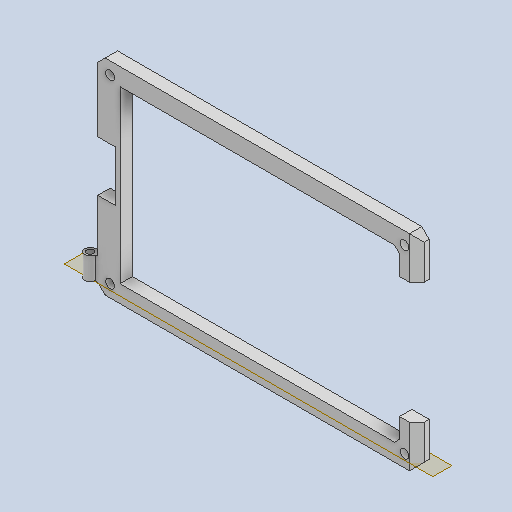
# Autodesk Inventor part: cap
Saved by Autodesk Inventor 2025 (Build 290162000, 162)
## iProperties
Created: 2026-10-22
Part Number: cap
Material: Типовые
Document SubType Name: Modeling
Designer: Leva
Density: 1 g/cm^3
Appearance: По умолчанию
Author: Leva
Autodesk Inventor part; units mm, degrees
ref_plane "YZ Plane" through (0, 0, 0) normal (1, 0, 0) x (0, 1, 0)
ref_plane "XZ Plane" through (0, 0, 0) normal (0, 1, 0) x (-1, 0, 0)
ref_plane "XY Plane" through (0, 0, 0) normal (0, 0, 1) x (1, 0, 0)
sketch "Эскиз1" plane through (0, 0, 0) normal (0, 0, 1) x (1, 0, 0)
  line L0 (82.923, -27.9995) -> (82.923, 49.0005) projected
  line L1 (85.923, 52.0005) -> (208.923, 52.0005) projected
  line L2 (211.923, 49.0005) -> (211.923, -27.9995) projected
  line L3 (208.923, -30.9995) -> (85.923, -30.9995) projected
  circle A0 centre (206.923, 47.0005) radius 1.35 construction
  circle A1 centre (87.923, 47.0005) radius 1.35 construction
  circle A2 centre (87.923, -25.9995) radius 1.35 construction
  circle A3 centre (206.923, -25.9995) radius 1.35 construction
  line L4 (204.923, -21.9995) -> (204.923, 43.0005)
  line L5 (202.923, 45.0005) -> (91.923, 45.0005)
  line L6 (89.923, 43.0005) -> (89.923, -21.9995)
  line L7 (91.923, -23.9995) -> (202.923, -23.9995)
  line L8 (204.923, -21.9995) -> (202.923, -23.9995)
  line L9 (204.923, 43.0005) -> (202.923, 45.0005)
  line L10 (91.923, 45.0005) -> (89.923, 43.0005)
  line L11 (91.923, -23.9995) -> (89.923, -21.9995)
  circle A4 centre (206.923, -25.9995) radius 1.8
  circle A5 centre (206.923, 47.0005) radius 1.8
  circle A6 centre (87.923, -25.9995) radius 1.8
  line L12 (85.923, 52.0005) -> (82.923, 49.0005) projected
  line L13 (211.923, 49.0005) -> (208.923, 52.0005) projected
  line L14 (208.923, -30.9995) -> (211.923, -27.9995) projected
  line L15 (82.923, -27.9995) -> (85.923, -30.9995) projected
  circle A7 centre (87.923, 47.0005) radius 1.8
  line L16 (204.923, -21.9995) -> (204.923, -13.9995) construction
  line L17 (204.923, -13.9995) -> (211.923, -13.9995)
  line L18 (211.923, 10.5005) -> (82.923, 10.5005) construction
  line L19 (204.923, 35.0005) -> (211.923, 35.0005)
  line L20 (83.923, 4.4505) -> (89.023, 4.4505) projected
  line L21 (89.023, 20.9105) -> (83.923, 20.9105) projected
  line L22 (83.923, 4.4505) -> (82.923, 4.4505) construction
  line L23 (82.923, 4.4505) -> (82.923, 2.4505) construction
  line L24 (82.923, 2.4505) -> (83.923, 2.4505) construction
  line L25 (83.923, 2.4505) -> (83.923, 4.4505) construction
  line L26 (82.923, 2.4505) -> (89.923, 2.4505)
  line L27 (83.923, 4.4505) -> (83.923, 20.651) construction
  line L28 (83.923, 20.9105) -> (82.923, 20.9105) construction
  line L29 (82.923, 20.9105) -> (82.923, 22.9105) construction
  line L30 (82.923, 22.9105) -> (83.923, 22.9105) construction
  line L31 (83.923, 22.9105) -> (83.923, 20.9105) construction
  line L32 (82.923, 22.9105) -> (89.923, 22.9105)
  line L33 (91.923, -23.9995) -> (91.923, 45.0005)
  point P0 (0, 0)
  point P1 (204.923, -23.9995)
  point P2 (204.923, 45.0005)
  point P3 (89.923, 45.0005)
  point P4 (89.923, -23.9995)
  point P5 (211.923, 35.0005)
  dimension "d0" = 7
  dimension "d1" = 2
  dimension "d2" = 2
  dimension "d3" = 2
  dimension "d4" = 2
  dimension "d5" = 2
  dimension "d6" = 2
  dimension "d7" = 2
  dimension "d8" = 2
  dimension "d9" = 3.6
  dimension "d10" = 3.6
  dimension "d12" = 3.6
  dimension "d13" = 3.6
  dimension "d16" = 8
  dimension "d30" = 1
  dimension "d31" = 2
  dimension "d32" = 1
  dimension "d33" = 2
  constraints: 48 end point, 12 point on line, 5 perpendicular, 4 centre point, 4 coincident, 4 parallel, 2 horizontal, 2 midpoint, 2 symmetric about line, 1 vertical, 3 other
  measures "d0" distance between parallel lines of L2 L4
  measures "d1" distance of L4.start point (204.923, -24)
  measures "d2" distance of L7.end point (204.923, -24)
  measures "d3" distance of L4.end point (204.923, 45)
  measures "d4" distance of L5.start point (204.923, 45)
  measures "d5" distance of L5.end point (89.923, 45)
  measures "d6" distance of L6.start point (89.923, 45)
  measures "d7" distance of L7.start point (89.923, -24)
  measures "d8" distance of L6.end point (89.923, -24)
  measures "d9" diameter of A4
  measures "d10" diameter of A5
  measures "d12" diameter of A6
  measures "d13" diameter of A7
  measures "d16" distance of L4.start L16.end
  measures "d30" distance of L24.end L23.end
  measures "d31" distance of L23.end L22.end
  measures "d32" distance of L29.end L30.end
  measures "d33" distance of L28.end L29.end
extrude "Выдавливание1" add sketch "Эскиз1" along normal blind 5 contours L0 L26 L6 L11 L7 L8 L4 L17 L2 L14 L3 L15 | L0 L12 L1 L13 L2 L19 L4 L9 L5 L10 L6 L32 | L6 L10 L33 L11
chamfer "Фаска1" distance 3 angle 45 2 edges at (211.923, -20.9995, 5) (211.923, 42.0005, 5)
ref_plane "РабПлоскость1" through (82.923, -27.9995, 0) normal (0, 1, 0) x (0, 0, 1)
sketch "Эскиз3" plane through (82.923, -27.9995, 0) normal (0, 1, 0) x (0, 0, 1)
  line L0 (0, -1.1064) -> (0, 0) construction
  line L1 (0, 0) -> (0.15, 0) construction
  line L2 (0.15, 0) -> (0.15, -3.251) construction
  line L3 (0.15, -3.251) -> (0, -3.251) construction
  line L4 (0, -3.251) -> (0, 0) construction
  circle A0 centre (0.15, -3.251) radius 1.35
  circle A1 centre (0.15, -3.251) radius 2.15
  line L5 (0, -1.1064) -> (0, 0)
  line L6 (0, 0) -> (5, 0) projected
  line L7 (0, 0) -> (5, 0)
  line L8 (0.15, -3.251) -> (2.3, -3.251)
  line L9 (5, 0) -> (2.2999, -3.2512) projected
  line L10 (5, 0) -> (2.3, -3.251)
  line L11 (2.5, 0) -> (2.5, -1) construction
  line L12 (5, -1.1064) -> (5, 0) construction
  line L13 (5, 0) -> (4.85, 0) construction
  line L14 (4.85, 0) -> (4.85, -3.251) construction
  line L15 (4.85, -3.251) -> (5, -3.251) construction
  line L16 (5, -3.251) -> (5, 0) construction
  circle A2 centre (4.85, -3.251) radius 1.35
  circle A3 centre (4.85, -3.251) radius 2.15
  line L17 (5, -1.1064) -> (5, 0)
  line L18 (5, 0) -> (0, 0)
  line L19 (4.85, -3.251) -> (2.7, -3.251)
  line L20 (0, 0) -> (2.7001, -3.2512)
  line L21 (0, 0) -> (2.7, -3.251)
  point P0 (0, -82.923)
  point P1 (0, -1.1062)
  point P2 (5, -1.1062)
  dimension "d27" = 4.3
  dimension "d24" = 0.15
  dimension "d25" = 3.251
  dimension "d26" = 2.7
  dimension "d34" = 1
  constraints: 38 end point, 10 symmetric about line, 4 coincident, 3 horizontal, 2 centre point, 2 parallel, 2 vertical, 1 collinear, 1 midpoint, 1 perpendicular, 7 other
  measures "d24" distance of L2.end L3.end
  measures "d25" distance of L1.end L2.end
  measures "d26" diameter of A0
  measures "d34" distance of L11.start L11.end
extrude "Выдавливание3" add sketch "Эскиз3" along normal blind 9 contours L20 A1 | A1 L20 L6 L9 A3 | L9 A3 L20 | A3 L9 | L9 A3 | L17 A3 L9 picked at (1.791, -2.0831)
equation "\"d2\" = d1"
equation "\"d4\" = d3"
equation "\"d5\" = d3"
equation "\"d6\" = d5"
equation "\"d7\" = d3"
equation "\"d8\" = d7"
